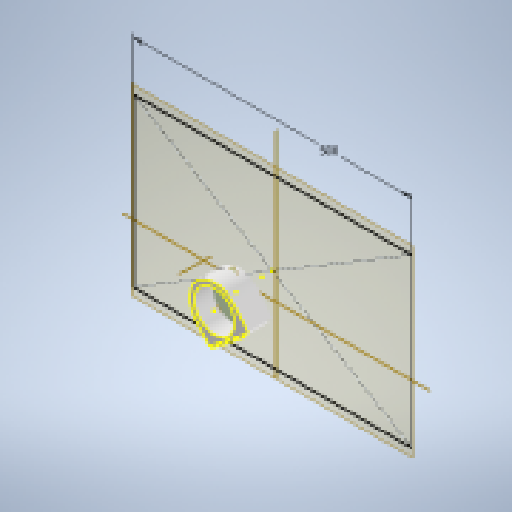
# Autodesk Inventor part: крепление мотора_часть 1
Saved by Autodesk Inventor 2024.2 (Build 282272000, 272)
## iProperties
Created: 2026-10-15
Part Number: крепление мотора_часть 1
Material: Типовые
Document SubType Name: Modeling
Designer: katya_notebook
Density: 1 g/cm^3
Appearance: По умолчанию
Author: katya_notebook
Autodesk Inventor part; units mm, degrees
ref_plane "YZ Plane" through (0, 0, 0) normal (1, 0, 0) x (0, 1, 0)
ref_plane "РабПлоскость1" through (0, 0, 0) normal (0, 0, 1) x (1, 0, 0)
sketch "Эскиз1" plane through (0, 0, 0) normal (0, 0, 1) x (1, 0, 0)
  line L0 (-250, 150) -> (250, 150)
  line L1 (250, 150) -> (250, -150)
  line L2 (250, -150) -> (-250, -150)
  line L3 (-250, -150) -> (-250, 150)
  line L4 (-250, 150) -> (250, -150) construction
  line L5 (250, 150) -> (-250, -150) construction
  line L6 (-230, -150) -> (230, -150) projected
  point P0 (0, 0)
  dimension "d0" = 500
  constraints: 12 end point, 2 midpoint, 2 parallel, 1 horizontal, 1 perpendicular, 1 point on line
  measures "d0" distance of L1.end L2.end
ref_plane "РабПлоскость2" through (0, 197.859, -8) normal (-1, 0, 0) x (0, 0, 1)
ref_plane "РабПлоскость3" through (250, -52.141, -8) normal (0, 1, 0) x (-1, 0, 0)
ref_plane "РабПлоскость4" through (-40, -50, 30) normal (0, 0, -1) x (0.706704, -0.7075094, 0)
sketch "Эскиз2" plane through (-40, -50, 30) normal (0, 0, -1) x (0.706704, -0.7075094, 0)
  circle A0 centre (0, 0) radius 33.25 projected
  circle A1 centre (0, 0) radius 10.5 projected
  circle A2 centre (0, -20) radius 1.25 projected
  circle A3 centre (-20, 0) radius 1.25 projected
  circle A4 centre (0, 20) radius 1.25 projected
  circle A5 centre (20, 0) radius 1.25 projected
  circle A6 centre (0, 0) radius 35.25 projected
  circle A7 centre (0, 0) radius 36.25
  point P0 (-7.1073, -63.6355)
  dimension "d64" = 72.5
  constraints: 1 centre point, 1 coincident
  measures "d64" diameter of A7
extrude "Выдавливание1" add sketch "Эскиз2" along normal blind 10 contours A0 | A6 | A7
sketch "Эскиз3" plane through (-40, -50, 20) normal (0, 0, -1) x (-1, 0, 0)
  circle A0 centre (0, 0) radius 37.625
  circle A1 centre (-80, 0) radius 35.25 projected
  circle A2 centre (0, 0) radius 10.5 projected
  circle A3 centre (0, 0) radius 36.25
  point P0 (-40, 50)
  dimension "d4" = 75.25
  dimension "d5" = 72.5
  constraints: 2 centre point, 1 coincident
  measures "d4" diameter of A0
  measures "d5" diameter of A3
extrude "Выдавливание2" add sketch "Эскиз3" against normal blind 45 contours A0
sketch "Эскиз4" plane through (-40, -50, 30) normal (0, 0, 1) x (1, 0, 0)
  circle A0 centre (0, 0) radius 10.5 projected
  point P0 (40, 50)
extrude "Выдавливание3" add sketch "Эскиз4" against normal up to surface (10 mm away)
sketch "Эскиз5" plane through (-40, -50, 20) normal (0, 0, -1) x (-1, 0, 0)
  arc A0 (-25, -37.4166) -> (-25, 37.4166) centre (0, 0) ccw
  line L0 (-25, 37.4166) -> (-25, -37.4166)
  line L1 (0, -45) -> (0, 45)
  circle A1 centre (0, 0) radius 37.625 projected
  circle A2 centre (-14.1502, 14.1341) radius 1.25 projected
  circle A3 centre (14.1341, 14.1502) radius 1.25 projected
  circle A4 centre (14.1502, -14.1341) radius 1.25 projected
  circle A5 centre (-14.1341, -14.1502) radius 1.25 projected
  point P0 (-40, 50)
  point P1 (-25, -28.1183)
  point P2 (-25, 28.1183)
  dimension "d10" = 90
  dimension "d11" = 25
  constraints: 4 end point, 4 point on circle, 2 vertical, 1 centre point, 1 midpoint, 1 other
  measures "d10" diameter of A0
  measures "d11" distance between parallel lines of L0 L1
extrude "Выдавливание4" add sketch "Эскиз5" against normal up to surface (45 mm away) contours L0 A1 L1 A0 | L1 A1 A0 | L1 A1 L0 A0
sketch "Эскиз6" plane through (-40, -50, 65) normal (0, 0, 1) x (1, 0, 0)
  arc A0 (25, -99.8665) -> (25, -25.0334) centre (50, -62.45) ccw projected
  arc A1 (25, -34.3316) -> (25, -90.5683) centre (50, -62.45) ccw projected
  line L0 (25, -25.0334) -> (25, -34.3316) projected
  line L1 (25, -90.5683) -> (25, -99.8665) projected
  arc A2 (25, 37.4166) -> (25, -37.4166) centre (0, 0) ccw projected
  line L2 (25, -37.4166) -> (25, -28.1183) projected
  point P0 (40, 50)
  point P1 (19.3503, -40.6272)
extrude "Выдавливание5" cut sketch "Эскиз6" against normal blind 65 contours A1 L2 A2
sketch "Эскиз7" plane through (-40, -50, 65) normal (0, 0, 1) x (1, 0, 0)
  arc A0 (25, -34.3316) -> (19.3503, -40.6272) centre (50, -62.45) ccw projected
  line L0 (25, -34.3316) -> (25, -28.1183) projected
  arc A1 (25, -28.1183) -> (25, 28.1183) centre (0, 0) ccw projected
  line L1 (25, 28.1183) -> (25, 37.4166) projected
  arc A2 (25, 37.4166) -> (19.3503, -40.6272) centre (0, 0) ccw projected
  circle A3 centre (0, 0) radius 36.25 projected
  circle A4 centre (0, 0) radius 45
  arc A5 (25, -99.8665) -> (30.6497, -21.8228) centre (50, -62.45) ccw projected
  point P0 (40, 50)
  point P1 (41.093, -18.3403)
  constraints: 1 coincident, 3 other
extrude "Выдавливание6" add sketch "Эскиз7" against normal blind 45 contours A4 A5 A1 L1
sketch "Эскиз8" plane through (-40, -50, 20) normal (0, 0, -1) x (-0.7075094, -0.706704, 0)
  arc A0 (15.0209, -42.419) -> (-16.1125, -42.0165) centre (0, 0) ccw projected
  line L0 (8.7582, -79.5191) -> (0, 0)
  line L1 (0, 0) -> (-80.5348, -8.87)
  line L2 (-16.1125, -42.0165) -> (24.8707, -37.5026)
  line L3 (-16.1125, -42.0165) -> (-40.3504, -44.686)
  line L4 (-44.7295, -4.9265) -> (-35.9713, -84.4464)
  line L5 (-44.7295, -4.9265) -> (-53.4878, 74.5935)
  line L6 (-4.9265, 44.7295) -> (-49.656, 39.803)
  line L7 (24.8707, -37.5026) -> (49.1086, -34.8331)
  line L8 (49.1086, -34.8331) -> (40.3504, 44.686)
  line L9 (-4.9265, 44.7295) -> (87.2561, 54.8824)
  line L10 (40.3504, 44.686) -> (39.803, 49.656)
  point P0 (-63.6355, 7.1073)
  point P1 (44.7295, 4.9265)
  dimension "d19" = 90
  dimension "d20" = 90
  dimension "d21" = 90
  dimension "d22" = 90
  dimension "d23" = 0
  dimension "d24" = 0
  constraints: 22 end point, 4 point on line, 3 perpendicular, 3 point on circle, 1 collinear, 1 midpoint, 1 parallel, 1 tangent
  measures "d19" angle of L9 L8
  measures "d20" angle of L6 L5
  measures "d21" angle of L4 L3
  measures "d22" angle of L8 L7
  measures "d23" distance edge to line of A0 L5
  measures "d24" distance from line of L1 point (44.73, 4.926)
extrude "Выдавливание7" add sketch "Эскиз8" against normal blind 45 contours L9 L10 L8 A0 | A0 L5 L6 | A0 L3 L4 | L8 L7 A0
sketch "Эскиз9" plane through (-40, -50, 20) normal (0, 0, -1) x (-0.7075094, -0.706704, 0)
  arc A0 (15.0209, -42.419) -> (6.5746, -41.9575) centre (8.7582, -79.5191) ccw projected
  arc A1 (15.0209, -42.419) -> (24.8707, -37.5026) centre (0, 0) ccw projected
  line L0 (24.8707, -37.5026) -> (49.1086, -34.8331) projected
  line L1 (49.1086, -34.8331) -> (39.803, 49.656) projected
  line L2 (39.803, 49.656) -> (-49.656, 39.803) projected
  line L3 (-49.656, 39.803) -> (-44.7295, -4.9265) projected
  line L4 (-44.7295, -4.9265) -> (-40.3504, -44.686) projected
  line L5 (-40.3504, -44.686) -> (-16.1125, -42.0165) projected
  arc A2 (-6.2627, -37.1001) -> (-16.1125, -42.0165) centre (8.7582, -79.5191) ccw projected
  arc A3 (-6.2627, -37.1001) -> (2.1836, -37.5616) centre (0, 0) ccw projected
  line L6 (2.1836, -37.5616) -> (6.5746, -41.9575) projected
  circle A4 centre (-20, 0) radius 1.25 projected
  circle A5 centre (0, 20) radius 1.25 projected
  circle A6 centre (20, 0) radius 1.25 projected
  circle A7 centre (0, -20) radius 1.25 projected
  line L7 (-40.3504, -44.686) -> (49.1086, -34.8331)
  point P0 (-63.6355, 7.1073)
  point P1 (24.8707, -37.5026)
  point P2 (4.3791, -39.7596)
  constraints: 2 end point, 1 perpendicular
extrude "Выдавливание8" cut sketch "Эскиз9" against normal blind 45 contours A0 L6 L7 A1
sketch "Эскиз10" plane through (-40, -50, 20) normal (0, 0, -1) x (-0.7075094, -0.706704, 0)
  arc A0 (-6.2627, -37.1001) -> (-16.1125, -42.0165) centre (8.7582, -79.5191) ccw projected
  arc A1 (-6.2627, -37.1001) -> (2.1836, -37.5616) centre (0, 0) ccw projected
  line L0 (2.1836, -37.5616) -> (4.3791, -39.7596) projected
  line L1 (4.3791, -39.7596) -> (-16.1125, -42.0165)
  point P0 (-63.6355, 7.1073)
  constraints: 2 end point
extrude "Выдавливание9" add sketch "Эскиз10" against normal blind 45
sketch "Эскиз12" plane through (-40, -50, 20) normal (0, 0, -1) x (-0.7075094, -0.706704, 0)
  circle A0 centre (0, -20) radius 1.25 projected
  circle A1 centre (20, 0) radius 1.25 projected
  circle A2 centre (0, 20) radius 1.25 projected
  circle A3 centre (-20, 0) radius 1.25 projected
  circle A4 centre (0, -20) radius 4
  circle A5 centre (20, 0) radius 4
  circle A6 centre (-20, 0) radius 4
  circle A7 centre (0, 20) radius 4
  point P0 (-63.6355, 7.1073)
  dimension "d31" = 8
  constraints: 4 centre point, 4 coincident, 3 equal radius
  measures "d31" diameter of A4
extrude "Выдавливание10" add sketch "Эскиз12" against normal up to surface (10 mm away) contours A0 | A1 | A2 | A3
sketch "Эскиз13" plane through (-40, -50, 20) normal (0, 0, -1) x (-0.7075094, -0.706704, 0)
  point P0 (-63.6355, 7.1073)
sketch "Эскиз14" plane through (-40, -50, 20) normal (0, 0, -1) x (-0.7075094, -0.706704, 0)
  circle A0 centre (-12.5, -15.6125) radius 1.25 projected
  circle A1 centre (-15.6125, 12.5) radius 1.25 projected
  circle A2 centre (15.6125, -12.5) radius 1.25 projected
  circle A3 centre (12.5, 15.6125) radius 1.25 projected
  point P0 (-63.6355, 7.1073)
sketch "Эскиз15" plane through (-40, -50, 65) normal (0, 0, 1) x (1, 0, 0)
  circle A0 centre (0, 0) radius 36.25 projected
  line L0 (-10.1281, -59.35) -> (60.1281, -3.1) projected
  line L1 (60.1281, -3.1) -> (35.1281, 28.125) projected
  line L2 (35.1281, 28.125) -> (7.0031, 63.2531) projected
  line L3 (7.0031, 63.2531) -> (-63.2531, 7.0031) projected
  line L4 (-63.2531, 7.0031) -> (-10.1281, -59.35) projected
  line L5 (-10.1281, -59.35) -> (14.8719, -90.575) projected
  line L6 (14.8719, -90.575) -> (42.9969, -125.7031) projected
  line L7 (42.9969, -125.7031) -> (113.2531, -69.4531) projected
  line L8 (113.2531, -69.4531) -> (60.1281, -3.1) projected
  point P0 (40, 50)
  point P1 (-10.1281, -59.35)
sketch "Эскиз16" plane through (-40, -50, 65) normal (0, 0, 1) x (1, 0, 0)
  circle A0 centre (0, 0) radius 36.25 projected
  line L0 (-10.1281, -59.35) -> (60.1281, -3.1) projected
  line L1 (60.1281, -3.1) -> (35.1281, 28.125) projected
  line L2 (35.1281, 28.125) -> (7.0031, 63.2531) projected
  line L3 (7.0031, 63.2531) -> (-63.2531, 7.0031) projected
  line L4 (-63.2531, 7.0031) -> (-10.1281, -59.35) projected
  line L5 (25, -31.225) -> (-10.1281, -59.35)
  line L6 (-4.2734, -54.6625) -> (-4.8959, -60.285)
  line L7 (-4.8959, -60.285) -> (6.8134, -50.91)
  line L8 (6.8134, -50.91) -> (1.1909, -50.2875)
  line L9 (-10.1281, -59.35) -> (60.1281, -3.1) projected
  line L10 (11.3391, -42.1625) -> (10.7166, -47.785)
  line L11 (10.7166, -47.785) -> (22.4259, -38.41)
  line L12 (22.4259, -38.41) -> (16.8034, -37.7875)
  line L13 (26.9515, -29.6625) -> (26.329, -35.285)
  line L14 (26.329, -35.285) -> (38.0384, -25.91)
  line L15 (38.0384, -25.91) -> (32.4159, -25.2875)
  line L16 (42.564, -17.1625) -> (41.9415, -22.785)
  line L17 (41.9415, -22.785) -> (53.6509, -13.41)
  line L18 (53.6509, -13.41) -> (48.0284, -12.7875)
  line L19 (58.1765, -4.6625) -> (57.554, -10.285)
  line L20 (57.554, -10.285) -> (69.2634, -0.91)
  line L21 (69.2634, -0.91) -> (63.6409, -0.2875)
  line L22 (62.6281, -6.2225) -> (60.1281, -3.1)
  line L23 (25, -31.225) -> (125.4629, 49.2097)
  line L24 (-4.2734, -54.6625) -> (1.1909, -50.2875)
  line L25 (-10.1281, -59.35) -> (60.1281, -3.1)
  point P0 (40, 50)
  point P1 (32.4159, -25.2875)
  point P2 (26.9515, -29.6625)
  point P3 (16.8034, -37.7875)
  point P4 (11.3391, -42.1625)
  point P5 (1.1909, -50.2875)
  point P6 (-4.2734, -54.6625)
  dimension "d40" = 45
  dimension "d41" = 45
  dimension "d42" = 35.1281
  dimension "d43" = 5.8547
  dimension "d46" = 11.7093
  dimension "d47" = 4
  dimension "d53" = 20
  constraints: 40 end point, 4 point on line, 3 collinear, 2 midpoint, 1 parallel, 29 other
  measures "d40" angle of L6 L0
  measures "d41" angle of L0 L8
  measures "d42" horizontal distance of L0.start L23.start
  measures "d43" horizontal distance of L6.start L0.start
  measures "d46" horizontal distance of L7.end L6.end
  measures "d47" distance between parallel lines of L0 L7
  measures "d53" distance of L6.start L10.start
extrude "Выдавливание13" add sketch "Эскиз16" against normal blind 45 contours L0 L8 L7 L6 | L0 L12 L11 L10 | L0 L15 L14 L13 | L18 L17 L16 L0
fillet "Сопряжение1" radius 45 2 edges at (-103.2531, -42.9969, 42.5) (-32.9969, 13.2531, 42.5)
sketch "Эскиз17" plane through (-40, -50, 20) normal (0, 0, -1) x (-0.7075094, -0.706704, 0)
  circle A0 centre (15.6361, 19.5067) radius 1.25 projected
  circle A1 centre (19.5067, -15.6361) radius 1.25 projected
  circle A2 centre (-15.6361, -19.5067) radius 1.25 projected
  circle A3 centre (-19.5067, 15.6361) radius 1.25 projected
  circle A4 centre (19.5067, -15.6361) radius 1.5
  circle A5 centre (15.6361, 19.5067) radius 1.5
  circle A6 centre (-19.5067, 15.6361) radius 1.5
  circle A7 centre (-15.6361, -19.5067) radius 1.5
  point P0 (-63.6355, 7.1073)
  dimension "d58" = 3
  constraints: 4 centre point, 4 coincident, 3 equal radius
  measures "d58" diameter of A4
extrude "Выдавливание14" cut sketch "Эскиз17" against normal blind 45 contours A0 | A1 | A2 | A3 | A4 | A5 | A6 | A7
sketch "Эскиз18" plane through (-40, -50, 20) normal (0, 0, -1) x (-0.7075094, -0.706704, 0)
  circle A0 centre (15.6361, 19.5067) radius 1.5 projected
  circle A1 centre (-19.5067, 15.6361) radius 1.5 projected
  circle A2 centre (-15.6361, -19.5067) radius 1.5 projected
  circle A3 centre (19.5067, -15.6361) radius 1.5 projected
  circle A4 centre (15.6361, 19.5067) radius 4
  circle A5 centre (19.5067, -15.6361) radius 4
  circle A6 centre (-15.6361, -19.5067) radius 4
  circle A7 centre (-19.5067, 15.6361) radius 4
  point P0 (-63.6355, 7.1073)
  dimension "d61" = 8
  constraints: 4 centre point, 4 coincident, 3 equal radius
  measures "d61" diameter of A4
extrude "Выдавливание15" cut sketch "Эскиз18" against normal blind 5
ref_plane "РабПлоскость5" through (-91.1609, -14.1, 20) normal (0.6250001, -0.7806247, 0) x (0.7806247, 0.6250001, 0)
sketch "Эскиз19" plane through (-91.1609, -14.1, 20) normal (0.6250001, -0.7806247, 0) x (0.7806247, 0.6250001, 0)
  line L0 (29.5075, 17.5) -> (29.5075, 12) projected
  line L1 (4.8364, 17.5) -> (30.1637, 17.5) projected
  line L2 (4.1205, 17.75) -> (4.1205, 10.25) projected
  line L3 (31, 45) -> (31, 0) projected
  line L4 (31, 18.7682) -> (1, 18.7682)
  line L5 (1, 18.7682) -> (1, 10.25)
  line L6 (1, 10.25) -> (31, 10.25)
  line L7 (31, 10.25) -> (31, 18.7682)
  point P0 (79.975, -20)
  dimension "d66" = 30
  constraints: 8 end point, 2 parallel, 2 point on line, 1 horizontal, 1 perpendicular
  measures "d66" distance of L4.start L4.end
extrude "Выдавливание16" cut sketch "Эскиз19" along normal blind 50
sketch "Эскиз20" plane through (-40, -50, 65) normal (0, 0, 1) x (1, 0, 0)
  circle A0 centre (0, 0) radius 36.25 projected
  arc A1 (35.1281, 28.125) -> (-35.1281, -28.125) centre (0, 0) ccw projected
  line L0 (-35.1281, -28.125) -> (-10.1281, -59.35) projected
  line L1 (-10.1281, -59.35) -> (-4.2734, -54.6625) projected
  line L2 (-4.2734, -54.6625) -> (-4.8959, -60.285) projected
  line L3 (-4.8959, -60.285) -> (6.8134, -50.91) projected
  line L4 (6.8134, -50.91) -> (1.1909, -50.2875) projected
  line L5 (1.1909, -50.2875) -> (11.3391, -42.1625) projected
  line L6 (11.3391, -42.1625) -> (10.7166, -47.785) projected
  line L7 (10.7166, -47.785) -> (22.4259, -38.41) projected
  line L8 (22.4259, -38.41) -> (16.8034, -37.7875) projected
  line L9 (16.8034, -37.7875) -> (26.9515, -29.6625) projected
  line L10 (26.9515, -29.6625) -> (26.329, -35.285) projected
  line L11 (26.329, -35.285) -> (38.0384, -25.91) projected
  line L12 (38.0384, -25.91) -> (32.4159, -25.2875) projected
  line L13 (32.4159, -25.2875) -> (42.564, -17.1625) projected
  line L14 (42.564, -17.1625) -> (41.9415, -22.785) projected
  line L15 (41.9415, -22.785) -> (53.6509, -13.41) projected
  line L16 (53.6509, -13.41) -> (48.0284, -12.7875) projected
  line L17 (48.0284, -12.7875) -> (60.1281, -3.1) projected
  line L18 (60.1281, -3.1) -> (35.1281, 28.125) projected
  point P0 (40, 50)
ref_plane "РабПлоскость6" through (-106.0961, -116.0961, 63.3501) normal (0.0000001, 0.0000009, 1) x (0.9939893, -0.1094771, 0)
ref_plane "РабПлоскость7" through (-106.0961, -116.0961, 63.6001) normal (0.0000001, 0.0000009, 1) x (0.9939893, -0.1094771, 0)
extrude "Выдавливание18" cut sketch "Эскиз15" against normal blind 1.8 contours A0 | L4 L3 L2 L1 L0 | L0 L8 L7 L6 L5
